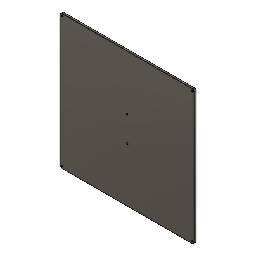
Y carriage (Autodesk Fusion 360 design; units mm, degrees)
Autodesk Fusion 360 part; units mm, degrees
sketch "Sketch1" plane through (0, 0, 0) normal (0, 0, 1) x (1, 0, 0)
  line L0 (2.8931, 216.1311) -> (213.1411, 216.1411)
  line L1 (0.1411, 213.1411) -> (0.1511, 2.8931)
  line L2 (3.1411, 0.1411) -> (213.3891, 0.1511)
  circle A0 centre (212.6411, 212.6411) radius 1.25
  circle A1 centre (108.1414, 87.1414) radius 1.25
  arc A2 (0.1511, 2.8931) -> (3.1411, 0.1411) centre (3.141, 3.1412) ccw
  circle A3 centre (3.6411, 3.6411) radius 1.25
  circle A4 centre (212.6411, 3.6411) radius 1.25
  circle A5 centre (108.1414, 128.1414) radius 1.25
  arc A6 (213.3891, 0.1511) -> (216.1411, 3.1411) centre (213.141, 3.141) ccw
  circle A7 centre (3.6411, 212.6411) radius 1.25
  arc A8 (216.1311, 213.3891) -> (213.1411, 216.1411) centre (213.3695, 213.389) ccw
  arc A9 (2.8931, 216.1311) -> (0.1411, 213.1411) centre (3.1412, 213.1413) ccw
  line L3 (216.1411, 3.1411) -> (216.1311, 213.3891)
extrude "Extrude1" add sketch "Sketch1" along normal blind 3
